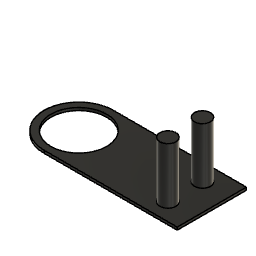
collarholder (Autodesk Fusion 360 design; units mm, degrees)
Autodesk Fusion 360 part; units mm, degrees
sketch "Esquisse1" plane through (0, 0, 0) normal (0, 0, 1) x (1, 0, 0)
  circle A0 centre (0, 0) radius 13
  line L0 (0, 13) -> (50, 13)
  line L1 (0, -13) -> (50, -13)
  line L2 (50, 13) -> (50, -13)
  circle A1 centre (0, 0) radius 10.5
  line L3 (0, 0) -> (40, 0) construction
  line L4 (40, 0) -> (40, -6.5) construction
  line L5 (40, 0) -> (40, 5.4983) construction
  circle A2 centre (40, 5.4983) radius 3
  circle A3 centre (40, -6.5) radius 3
  dimension "d1" = 26
  dimension "d2" = 50
  dimension "d3" = 50
  dimension "d4" = 21
  dimension "d5" = 40
  dimension "d6" = 6.5
  dimension "d7" = 6
  dimension "d8" = 6
  constraint coincident A0.centre A1.centre
  constraint coincident A0 L0.start
  constraint horizontal L0
  constraint coincident A0 L1.start
  constraint horizontal L1
  constraint perpendicular L1 L2
  constraint horizontal L3
  constraint perpendicular L3 L4
  constraint coincident L5.end A2.centre
  constraint coincident L4.end A3.centre
  measures "d1" diameter of A0
  measures "d2" distance of L0.start L0.end
  measures "d3" distance of L1.start L1.end
  measures "d4" diameter of A1
  measures "d5" distance of A0.centre L3.end
  measures "d6" distance of L3.end L4.end
  measures "d7" diameter of A2
  measures "d8" diameter of A3
extrude "Extrusion1" add sketch "Esquisse1" along normal blind 1 contours A0 | A0 L0 L1 L2 | A2 | A3
sketch "Esquisse2" plane through (0, 0, 1) normal (0, 0, 1) x (-1, 0, 0)
  circle A0 centre (0, 0) radius 10.5
  arc A1 (0, -13) -> (0, 13) centre (0, 0) ccw
  line L0 (0, 13) -> (-50, 13)
  line L1 (-50, 13) -> (-50, -13)
  line L2 (-50, -13) -> (0, -13)
  line L3 (0, 0) -> (-40, 0)
  line L4 (-40, 0) -> (-40, -6.5)
  line L5 (-40, 0) -> (-40, 6.5)
  circle A2 centre (-40, -6.5) radius 3
  circle A3 centre (-40, 6.5) radius 3
  dimension "d11" = 40
  dimension "d12" = 6.5
  dimension "d13" = 6.5
  dimension "d14" = 6
  dimension "d15" = 6
  constraint coincident A0.centre A1.centre
  constraint horizontal L3
  constraint perpendicular L3 L4
  constraint perpendicular L3 L5
  constraint coincident L4.end A2.centre
  constraint coincident L5.end A3.centre
  measures "d11" distance of A0.centre L3.end
  measures "d12" distance of L3.end L4.end
  measures "d13" distance of L3.end L5.end
  measures "d14" diameter of A2
  measures "d15" diameter of A3
extrude "Extrusion2" add sketch "Esquisse2" along normal blind 21 contours A2 | A3
